Autodesk Fusion 360 part; units mm, degrees
(part 2 of 3)
  spline S265 degree 3 poles (6.2269, 17.0813) (6.3936, 17.4543) (6.4412, 17.5178) (6.6238, 17.8353) knots 0 0 0 0 1 1 1 1
  spline S266 degree 3 poles (6.6238, 17.8353) (6.8064, 18.1528) (7.108, 18.645) (7.3382, 18.9863) knots 0 0 0 0 1 1 1 1
  spline S267 degree 3 poles (7.3382, 18.9863) (7.5684, 19.3276) (7.7985, 19.5975) (8.0129, 19.8594) knots 0 0 0 0 1 1 1 1
  spline S268 degree 3 poles (8.0129, 19.8594) (8.2272, 20.1213) (8.3859, 20.296) (8.6479, 20.5341) knots 0 0 0 0 1 1 1 1
  spline S269 degree 3 poles (8.6479, 20.5341) (8.9098, 20.7722) (9.2273, 21.05) (9.5607, 21.2881) knots 0 0 0 0 1 1 1 1
  spline S270 degree 3 poles (9.5607, 21.2881) (9.894, 21.5263) (10.2354, 21.7485) (10.6322, 21.9628) knots 0 0 0 0 1 1 1 1
  spline S271 degree 3 poles (10.6322, 21.9628) (11.0291, 22.1771) (11.4895, 22.3915) (11.9419, 22.5581) knots 0 0 0 0 1 1 1 1
  spline S272 degree 3 poles (11.9419, 22.5581) (12.3944, 22.7248) (12.9817, 22.8677) (13.331, 22.955) knots 0 0 0 0 1 1 1 1
  spline S273 degree 3 poles (13.331, 22.955) (13.6802, 23.0423) (13.7755, 23.0423) (14.0454, 23.0741) knots 0 0 0 0 1 1 1 1
  spline S274 degree 3 poles (14.0454, 23.0741) (14.3152, 23.1058) (14.5772, 23.1455) (14.9582, 23.1535) knots 0 0 0 0 1 1 1 1
  spline S275 degree 3 poles (14.9582, 23.1535) (15.3392, 23.1614) (16.0059, 23.1376) (16.3472, 23.1138) knots 0 0 0 0 1 1 1 1
  spline S276 degree 3 poles (16.3472, 23.1138) (16.6885, 23.09) (16.6489, 23.1217) (17.0219, 23.0344) knots 0 0 0 0 1 1 1 1
  spline S277 degree 3 poles (17.0219, 23.0344) (17.395, 22.9471) (18.1411, 22.7486) (18.5697, 22.5978) knots 0 0 0 0 1 1 1 1
  spline S278 degree 3 poles (18.5697, 22.5978) (18.9984, 22.447) (19.2524, 22.3121) (19.6016, 22.1216) knots 0 0 0 0 1 1 1 1
  spline S279 degree 3 poles (19.6016, 22.1216) (19.9509, 21.9311) (20.3398, 21.6771) (20.6732, 21.4469) knots 0 0 0 0 1 1 1 1
  spline S280 degree 3 poles (20.6732, 21.4469) (21.0065, 21.2167) (21.3002, 20.9786) (21.586, 20.7325) knots 0 0 0 0 1 1 1 1
  spline S281 degree 3 poles (21.586, 20.7325) (21.8717, 20.4865) (22.1337, 20.2325) (22.3797, 19.9785) knots 0 0 0 0 1 1 1 1
  spline S282 degree 3 poles (22.3797, 19.9785) (22.6258, 19.7245) (22.7925, 19.534) (23.0544, 19.1847) knots 0 0 0 0 1 1 1 1
  spline S283 degree 3 poles (23.0544, 19.1847) (23.3164, 18.8355) (23.6974, 18.3195) (23.9672, 17.875) knots 0 0 0 0 1 1 1 1
  spline S284 degree 3 poles (23.9672, 17.875) (24.2371, 17.4305) (24.4911, 16.9305) (24.6816, 16.5256) knots 0 0 0 0 1 1 1 1
  spline S285 degree 3 poles (24.6816, 16.5256) (24.8721, 16.1208) (24.9912, 15.7875) (25.1182, 15.4541) knots 0 0 0 0 1 1 1 1
  spline S286 degree 3 poles (25.1182, 15.4541) (25.2452, 15.1207) (25.3245, 14.9143) (25.4357, 14.5016) knots 0 0 0 0 1 1 1 1
  spline S287 degree 3 poles (25.4357, 14.5016) (25.5468, 14.0888) (25.6897, 13.4856) (25.7929, 12.9538) knots 0 0 0 0 1 1 1 1
  spline S288 degree 3 poles (25.7929, 12.9538) (25.896, 12.422) (25.9754, 11.7711) (26.031, 11.3266) knots 0 0 0 0 1 1 1 1
  spline S289 degree 3 poles (26.031, 11.3266) (26.0865, 10.8821) (26.0945, 10.7868) (26.1104, 10.2947) knots 0 0 0 0 1 1 1 1
  spline S290 degree 3 poles (26.1104, 10.2947) (26.1262, 9.8026) (26.1659, 9.2231) (26.1104, 8.35) knots 0 0 0 0 1 1 1 1
  spline S291 degree 3 poles (26.1104, 8.35) (26.0548, 7.4769) (25.8564, 5.6433) (25.7929, 5.056) knots 0 0 0 0 1 1 1 1
  spline S292 degree 3 poles (25.7929, 5.056) (25.7294, 4.4686) (25.769, 5.1512) (25.7135, 4.8178) knots 0 0 0 0 1 1 1 1
  spline S293 degree 3 poles (25.7135, 4.8178) (25.6579, 4.4845) (25.5468, 3.5081) (25.4754, 3.0319) knots 0 0 0 0 1 1 1 1
  spline S294 degree 3 poles (25.4754, 3.0319) (25.4039, 2.5556) (25.4357, 2.6668) (25.2769, 1.9603) knots 0 0 0 0 1 1 1 1
  spline S295 degree 3 poles (25.2769, 1.9603) (25.1182, 1.2539) (24.7848, -0.2304) (24.5229, -1.2147) knots 0 0 0 0 1 1 1 1
  spline S296 degree 3 poles (24.5229, -1.2147) (24.2609, -2.1989) (23.9672, -3.1355) (23.6894, -3.9531) knots 0 0 0 0 1 1 1 1
  spline S297 degree 3 poles (23.6894, -3.9531) (23.4116, -4.7707) (23.1179, -5.5247) (22.856, -6.1359) knots 0 0 0 0 1 1 1 1
  spline S298 degree 3 poles (22.856, -6.1359) (22.594, -6.7471) (22.4432, -7.0567) (22.1416, -7.6044) knots 0 0 0 0 1 1 1 1
  spline S299 degree 3 poles (22.1416, -7.6044) (21.84, -8.152) (21.3796, -8.914) (21.0304, -9.43) knots 0 0 0 0 1 1 1 1
  spline S300 degree 3 poles (21.0304, -9.43) (20.6811, -9.9459) (20.3715, -10.3269) (20.0382, -10.7) knots 0 0 0 0 1 1 1 1
  spline S301 degree 3 poles (20.0382, -10.7) (19.7048, -11.073) (19.4667, -11.335) (19.046, -11.6922) knots 0 0 0 0 1 1 1 1
  spline S302 degree 3 poles (19.046, -11.6922) (18.6253, -12.0494) (18.0141, -12.5335) (17.5379, -12.8431) knots 0 0 0 0 1 1 1 1
  spline S303 degree 3 poles (17.5379, -12.8431) (17.0616, -13.1527) (16.6012, -13.3749) (16.1885, -13.5575) knots 0 0 0 0 1 1 1 1
  spline S304 degree 3 poles (16.1885, -13.5575) (15.7757, -13.74) (15.4027, -13.8512) (15.0772, -13.9544) knots 0 0 0 0 1 1 1 1
  spline S305 degree 3 poles (15.0772, -13.9544) (14.7518, -14.0575) (14.5851, -14.1052) (14.2438, -14.1528) knots 0 0 0 0 1 1 1 1
  spline S306 degree 3 poles (14.2438, -14.1528) (13.9025, -14.2004) (13.3786, -14.2401) (13.0135, -14.2322) knots 0 0 0 0 1 1 1 1
  spline S307 degree 3 poles (18.411, -26.0987) (19.2603, -25.678) (20.1175, -25.17) (20.7129, -24.8287) knots 0 0 0 0 1 1 1 1
  spline S308 degree 3 poles (20.7129, -24.8287) (21.3082, -24.4874) (21.3796, -24.4557) (21.9829, -24.035) knots 0 0 0 0 1 1 1 1
  spline S309 degree 3 poles (21.9829, -24.035) (22.5861, -23.6143) (23.5783, -22.9237) (24.3244, -22.3284) knots 0 0 0 0 1 1 1 1
  spline S310 degree 3 poles (24.3244, -22.3284) (25.0705, -21.7331) (25.7452, -21.1457) (26.4675, -20.4631) knots 0 0 0 0 1 1 1 1
  spline S311 degree 3 poles (26.4675, -20.4631) (27.1899, -19.7805) (28.1106, -18.82) (28.6504, -18.2406) knots 0 0 0 0 1 1 1 1
  spline S312 degree 3 poles (28.6504, -18.2406) (29.1901, -17.6612) (29.3806, -17.3992) (29.7219, -16.9706) knots 0 0 0 0 1 1 1 1
  spline S313 degree 3 poles (29.7219, -16.9706) (30.0632, -16.542) (30.2775, -16.288) (30.7141, -15.6609) knots 0 0 0 0 1 1 1 1
  spline S314 degree 3 poles (30.7141, -15.6609) (31.1507, -15.0339) (31.8333, -14.0575) (32.3413, -13.2003) knots 0 0 0 0 1 1 1 1
  spline S315 degree 3 poles (32.3413, -13.2003) (32.8493, -12.343) (33.3335, -11.4699) (33.77, -10.5412) knots 0 0 0 0 1 1 1 1
  spline S316 degree 3 poles (33.77, -10.5412) (34.2066, -9.6125) (34.6035, -8.66) (34.9607, -7.644) knots 0 0 0 0 1 1 1 1
  spline S317 degree 3 poles (34.9607, -7.644) (35.3179, -6.628) (35.6592, -5.4454) (35.9132, -4.4294) knots 0 0 0 0 1 1 1 1
  spline S318 degree 3 poles (35.9132, -4.4294) (36.1672, -3.4134) (36.3497, -2.5482) (36.5085, -1.5322) knots 0 0 0 0 1 1 1 1
  spline S319 degree 3 poles (36.5085, -1.5322) (36.6672, -0.5162) (36.8022, 0.5157) (36.8657, 1.6825) knots 0 0 0 0 1 1 1 1
  spline S320 degree 3 poles (36.8657, 1.6825) (36.9292, 2.8493) (36.953, 4.294) (36.9054, 5.4528) knots 0 0 0 0 1 1 1 1
  spline S321 degree 3 poles (36.9054, 5.4528) (36.8577, 6.6117) (36.691, 7.8261) (36.5879, 8.6278) knots 0 0 0 0 1 1 1 1
  spline S322 degree 3 poles (36.5879, 8.6278) (36.4847, 9.4295) (36.3894, 9.7311) (36.2704, 10.255) knots 0 0 0 0 1 1 1 1
  spline S323 degree 3 poles (36.2704, 10.255) (36.1513, 10.7789) (36.0799, 11.1043) (35.8735, 11.7631) knots 0 0 0 0 1 1 1 1
  spline S324 degree 3 poles (35.8735, 11.7631) (35.6671, 12.422) (35.4052, 13.3348) (35.04, 14.2238) knots 0 0 0 0 1 1 1 1
  spline S325 degree 3 poles (35.04, 14.2238) (34.6749, 15.1128) (34.1431, 16.232) (33.6907, 17.0813) knots 0 0 0 0 1 1 1 1
  spline S326 degree 3 poles (33.6907, 17.0813) (33.2382, 17.9306) (32.8017, 18.645) (32.3413, 19.3435) knots 0 0 0 0 1 1 1 1
  spline S327 degree 3 poles (32.3413, 19.3435) (31.8809, 20.042) (31.3888, 20.7087) (30.9522, 21.2881) knots 0 0 0 0 1 1 1 1
  spline S328 degree 3 poles (30.9522, 21.2881) (30.5157, 21.8676) (30.341, 22.1375) (29.7219, 22.7963) knots 0 0 0 0 1 1 1 1
  spline S329 degree 3 poles (29.7219, 22.7963) (29.1028, 23.4551) (27.9519, 24.6378) (27.2613, 25.2569) knots 0 0 0 0 1 1 1 1
  spline S330 degree 3 poles (27.2613, 25.2569) (26.5707, 25.876) (26.1818, 26.13) (25.5944, 26.5269) knots 0 0 0 0 1 1 1 1
  spline S331 degree 3 poles (25.5944, 26.5269) (25.007, 26.9238) (24.3085, 27.3365) (23.7291, 27.6381) knots 0 0 0 0 1 1 1 1
  spline S332 degree 3 poles (23.7291, 27.6381) (23.1497, 27.9398) (22.8322, 28.0906) (22.1416, 28.3525) knots 0 0 0 0 1 1 1 1
  spline S333 degree 3 poles (22.1416, 28.3525) (21.451, 28.6145) (20.062, 29.0431) (19.6016, 29.2256) knots 0 0 0 0 1 1 1 1
  spline S334 degree 3 poles (19.6016, 29.2256) (19.1412, 29.4082) (19.419, 29.3447) (19.3635, 29.4241) knots 0 0 0 0 1 1 1 1
  spline S335 degree 3 poles (19.3635, 29.4241) (19.3079, 29.5035) (19.2603, 28.416) (19.2444, 29.7019) knots 0 0 0 0 1 1 1 1
  spline S336 degree 3 poles (19.2444, 29.7019) (19.2285, 30.9878) (19.2285, 35.1232) (19.2444, 37.1235) knots 0 0 0 0 1 1 1 1
  spline S337 degree 3 poles (19.2444, 37.1235) (19.2603, 39.1237) (19.3317, 40.8223) (19.3238, 41.6875) knots 0 0 0 0 1 1 1 1
  spline S338 degree 3 poles (19.3238, 41.6875) (19.3159, 42.5527) (19.2762, 42.1161) (19.2047, 42.3225) knots 0 0 0 0 1 1 1 1
  spline S339 degree 3 poles (19.2047, 42.3225) (19.1333, 42.5289) (19.0142, 42.7511) (18.8872, 42.9178) knots 0 0 0 0 1 1 1 1
  spline S340 degree 3 poles (18.8872, 42.9178) (18.7602, 43.0845) (18.6015, 43.2195) (18.4507, 43.3147) knots 0 0 0 0 1 1 1 1
  spline S341 degree 3 poles (18.4507, 43.3147) (18.2999, 43.41) (18.1173, 43.4655) (17.9744, 43.5131) knots 0 0 0 0 1 1 1 1
  spline S342 degree 3 poles (17.9744, 43.5131) (17.8315, 43.5608) (18.3951, 43.5767) (17.5775, 43.5925) knots 0 0 0 0 1 1 1 1
  spline S343 degree 3 poles (17.5775, 43.5925) (16.76, 43.6084) (13.8787, 43.6163) (13.0532, 43.5925) knots 0 0 0 0 1 1 1 1
  spline S344 degree 3 poles (13.0532, 43.5925) (12.2277, 43.5687) (12.7515, 43.537) (12.6166, 43.4338) knots 0 0 0 0 1 1 1 1
  spline S345 degree 3 poles (12.6166, 43.4338) (12.4817, 43.3306) (12.3229, 43.156) (12.2197, 42.9575) knots 0 0 0 0 1 1 1 1
  spline S346 degree 3 poles (12.2197, 42.9575) (12.1165, 42.7591) (12.0927, 43.1242) (12.0213, 42.2431) knots 0 0 0 0 1 1 1 1
  spline S347 degree 3 poles (12.0213, 42.2431) (11.9499, 41.3621) (11.8467, 38.4808) (11.7832, 37.6791) knots 0 0 0 0 1 1 1 1
  spline S348 degree 3 poles (11.7832, 37.6791) (11.7197, 36.8774) (11.7435, 37.5203) (11.6641, 37.441) knots 0 0 0 0 1 1 1 1
  spline S349 degree 3 poles (11.6641, 37.441) (11.5847, 37.3616) (11.4022, 37.2425) (11.3069, 37.2028) knots 0 0 0 0 1 1 1 1
  spline S350 degree 3 poles (11.3069, 37.2028) (11.2117, 37.1631) (11.1402, 37.187) (11.0688, 37.2028) knots 0 0 0 0 1 1 1 1
  spline S351 degree 3 poles (11.0688, 37.2028) (10.9974, 37.2187) (10.9339, 37.2346) (10.8704, 37.2822) knots 0 0 0 0 1 1 1 1
  spline S352 degree 3 poles (10.8704, 37.2822) (10.8069, 37.3298) (10.7275, 37.4013) (10.6719, 37.4806) knots 0 0 0 0 1 1 1 1
  spline S353 degree 3 poles (10.6719, 37.4806) (10.6164, 37.56) (10.6164, 36.9965) (10.5529, 37.7585) knots 0 0 0 0 1 1 1 1
  spline S354 degree 3 poles (10.5529, 37.7585) (10.4894, 38.5205) (10.3385, 41.2113) (10.275, 42.0447) knots 0 0 0 0 1 1 1 1
  spline S355 degree 3 poles (10.275, 42.0447) (10.2115, 42.8781) (10.2036, 42.5845) (10.156, 42.7591) knots 0 0 0 0 1 1 1 1
  spline S356 degree 3 poles (10.156, 42.7591) (10.1084, 42.9337) (10.0687, 42.9813) (9.9972, 43.0766) knots 0 0 0 0 1 1 1 1
  spline S357 degree 3 poles (9.9972, 43.0766) (9.9258, 43.1718) (9.8623, 43.2671) (9.7194, 43.3544) knots 0 0 0 0 1 1 1 1
  spline S358 degree 3 poles (9.7194, 43.3544) (9.5765, 43.4417) (10.4259, 43.5528) (9.1638, 43.5925) knots 0 0 0 0 1 1 1 1
  spline S359 degree 3 poles (9.1638, 43.5925) (7.9017, 43.6322) (3.3853, 43.6163) (2.1391, 43.5925) knots 0 0 0 0 1 1 1 1
  spline S360 degree 3 poles (2.1391, 43.5925) (0.8929, 43.5687) (1.7819, 43.4893) (1.6629, 43.4338) knots 0 0 0 0 1 1 1 1
  spline S361 degree 3 poles (1.6629, 43.4338) (1.5438, 43.3782) (1.4882, 43.3068) (1.4247, 43.2353) knots 0 0 0 0 1 1 1 1
  spline S362 degree 3 poles (1.4247, 43.2353) (1.3612, 43.1639) (1.3215, 43.148) (1.266, 42.9972) knots 0 0 0 0 1 1 1 1
  spline S363 degree 3 poles (1.266, 42.9972) (1.2104, 42.8464) (1.131, 42.8543) (1.0675, 42.3225) knots 0 0 0 0 1 1 1 1
  spline S364 degree 3 poles (1.0675, 42.3225) (1.004, 41.7907) (0.9167, 40.5286) (0.8691, 39.7825) knots 0 0 0 0 1 1 1 1
  spline S365 degree 3 poles (0.8691, 39.7825) (0.8215, 39.0364) (0.8215, 38.2188) (0.7897, 37.8378) knots 0 0 0 0 1 1 1 1
  spline S366 degree 3 poles (0.7897, 37.8378) (0.758, 37.4568) (0.7342, 37.6156) (0.6707, 37.5203) knots 0 0 0 0 1 1 1 1
  spline S367 degree 3 poles (0.6707, 37.5203) (0.6072, 37.4251) (0.504, 37.3378) (0.4325, 37.2822) knots 0 0 0 0 1 1 1 1
  spline S368 degree 3 poles (0.4325, 37.2822) (0.3611, 37.2267) (0.3214, 37.2187) (0.2341, 37.2028) knots 0 0 0 0 1 1 1 1
  spline S369 degree 3 poles (0.2341, 37.2028) (0.1468, 37.187) (0.0039, 37.187) (-0.0834, 37.2028) knots 0 0 0 0 1 1 1 1
  spline S370 degree 3 poles (-0.0834, 37.2028) (-0.1707, 37.2187) (-0.2025, 37.2187) (-0.2818, 37.2822) knots 0 0 0 0 1 1 1 1
  spline S371 degree 3 poles (-0.2818, 37.2822) (-0.3612, 37.3457) (-0.5041, 37.4727) (-0.5596, 37.56) knots 0 0 0 0 1 1 1 1
  spline S372 degree 3 poles (-0.5596, 37.56) (-0.6152, 37.6473) (-0.5835, 37.0282) (-0.639, 37.7981) knots 0 0 0 0 1 1 1 1
  spline S373 degree 3 poles (-0.639, 37.7981) (-0.6946, 38.5681) (-0.8533, 41.3303) (-0.9168, 42.1638) knots 0 0 0 0 1 1 1 1
  spline S374 degree 3 poles (-0.9168, 42.1638) (-0.9803, 42.9972) (-0.9803, 42.6321) (-1.0359, 42.7988) knots 0 0 0 0 1 1 1 1
  spline S375 degree 3 poles (-1.0359, 42.7988) (-1.0915, 42.9655) (-1.1708, 43.0686) (-1.2343, 43.156) knots 0 0 0 0 1 1 1 1
  spline S376 degree 3 poles (-1.2343, 43.156) (-1.2978, 43.2433) (-1.2661, 43.2433) (-1.3931, 43.3147) knots 0 0 0 0 1 1 1 1
  spline S377 degree 3 poles (-1.3931, 43.3147) (-1.5201, 43.3861) (-0.6946, 43.5449) (-1.9884, 43.5925) knots 0 0 0 0 1 1 1 1
  spline S378 degree 3 poles (-1.9884, 43.5925) (-3.2822, 43.6401) (-7.8463, 43.6322) (-9.1321, 43.5925) knots 0 0 0 0 1 1 1 1
  spline S379 degree 3 poles (-9.1321, 43.5925) (-10.418, 43.5528) (-9.5528, 43.4496) (-9.6878, 43.3544) knots 0 0 0 0 1 1 1 1
  spline S380 degree 3 poles (-9.6878, 43.3544) (-9.8227, 43.2592) (-9.8783, 43.2115) (-9.9656, 43.0369) knots 0 0 0 0 1 1 1 1
  spline S381 degree 3 poles (-9.9656, 43.0369) (-10.0529, 42.8623) (-10.1085, 43.2036) (-10.2037, 42.3225) knots 0 0 0 0 1 1 1 1
  spline S382 degree 3 poles (-10.2037, 42.3225) (-10.299, 41.4415) (-10.4815, 38.5681) (-10.5609, 37.7585) knots 0 0 0 0 1 1 1 1
  spline S383 degree 3 poles (-10.5609, 37.7585) (-10.6403, 36.9488) (-10.6323, 37.5521) (-10.68, 37.4806) knots 0 0 0 0 1 1 1 1
  spline S384 degree 3 poles (-10.68, 37.4806) (-10.7276, 37.4092) (-10.7673, 37.3695) (-10.8387, 37.3219) knots 0 0 0 0 1 1 1 1
  spline S385 degree 3 poles (-10.8387, 37.3219) (-10.9101, 37.2743) (-11.0133, 37.2187) (-11.1165, 37.2028) knots 0 0 0 0 1 1 1 1
  spline S386 degree 3 poles (-11.1165, 37.2028) (-11.2197, 37.187) (-11.3308, 37.187) (-11.434, 37.2425) knots 0 0 0 0 1 1 1 1
  spline S387 degree 3 poles (-11.434, 37.2425) (-11.5372, 37.2981) (-11.688, 37.441) (-11.7515, 37.5203) knots 0 0 0 0 1 1 1 1
  spline S388 degree 3 poles (-11.7515, 37.5203) (-11.815, 37.5997) (-11.7753, 36.9012) (-11.8309, 37.7188) knots 0 0 0 0 1 1 1 1
  spline S389 degree 3 poles (-11.8309, 37.7188) (-11.8865, 38.5363) (-12.0214, 41.5526) (-12.1087, 42.4416) knots 0 0 0 0 1 1 1 1
  spline S390 degree 3 poles (-12.1087, 42.4416) (-12.196, 43.3306) (-12.2516, 42.8861) (-12.3468, 43.0369) knots 0 0 0 0 1 1 1 1
  spline S391 degree 3 poles (-12.3468, 43.0369) (-12.4421, 43.1877) (-12.5135, 43.2592) (-12.6643, 43.3544) knots 0 0 0 0 1 1 1 1
  spline S392 degree 3 poles (-12.6643, 43.3544) (-12.8151, 43.4496) (-12.4421, 43.5528) (-13.2596, 43.5925) knots 0 0 0 0 1 1 1 1
  spline S393 degree 3 poles (-13.2596, 43.5925) (-14.0772, 43.6322) (-16.7918, 43.6084) (-17.5856, 43.5925) knots 0 0 0 0 1 1 1 1
  spline S394 degree 3 poles (-17.5856, 43.5925) (-18.3793, 43.5767) (-17.8555, 43.5687) (-18.0221, 43.5131) knots 0 0 0 0 1 1 1 1
  spline S395 degree 3 poles (-18.0221, 43.5131) (-18.1888, 43.4576) (-18.419, 43.3782) (-18.5778, 43.275) knots 0 0 0 0 1 1 1 1
  spline S396 degree 3 poles (-18.5778, 43.275) (-18.7365, 43.1718) (-18.8556, 43.0686) (-18.9746, 42.9178) knots 0 0 0 0 1 1 1 1
  spline S397 degree 3 poles (-18.9746, 42.9178) (-19.0937, 42.767) (-19.2207, 42.5368) (-19.2921, 42.3622) knots 0 0 0 0 1 1 1 1
  spline S398 degree 3 poles (-19.2921, 42.3622) (-19.3636, 42.1876) (-19.3953, 42.8067) (-19.4112, 41.8463) knots 0 0 0 0 1 1 1 1
  spline S399 degree 3 poles (-19.4112, 41.8463) (-19.4271, 40.8858) (-19.3953, 37.9013) (-19.3715, 36.6075) knots 0 0 0 0 1 1 1 1
  spline S400 degree 3 poles (-19.3715, 36.6075) (-19.3477, 35.3137) (-19.308, 35.1946) (-19.2921, 34.0675) knots 0 0 0 0 1 1 1 1
  spline S401 degree 3 poles (-19.2921, 34.0675) (-19.2763, 32.9404) (-19.2683, 30.6147) (-19.2921, 29.8606) knots 0 0 0 0 1 1 1 1
  spline S402 degree 3 poles (-19.2921, 29.8606) (-19.316, 29.1066) (-19.3398, 29.6463) (-19.4112, 29.5431) knots 0 0 0 0 1 1 1 1
  spline S403 degree 3 poles (-19.4112, 29.5431) (-19.4826, 29.44) (-19.3001, 29.44) (-19.7287, 29.2653) knots 0 0 0 0 1 1 1 1
  spline S404 degree 3 poles (-19.7287, 29.2653) (-20.1573, 29.0907) (-21.4194, 28.7176) (-21.9909, 28.5113) knots 0 0 0 0 1 1 1 1
  spline S405 degree 3 poles (-21.9909, 28.5113) (-22.5624, 28.3049) (-22.6021, 28.297) (-23.1418, 28.035) knots 0 0 0 0 1 1 1 1
  spline S406 degree 3 poles (-23.1418, 28.035) (-23.6816, 27.7731) (-24.769, 27.1698) (-25.2056, 26.9238) knots 0 0 0 0 1 1 1 1
  spline S407 degree 3 poles (-25.2056, 26.9238) (-25.6421, 26.6777) (-25.412, 26.8206) (-25.7612, 26.5666) knots 0 0 0 0 1 1 1 1
  spline S408 degree 3 poles (-25.7612, 26.5666) (-26.1105, 26.3126) (-26.9121, 25.7014) (-27.309, 25.376) knots 0 0 0 0 1 1 1 1
  spline S409 degree 3 poles (-27.309, 25.376) (-27.7059, 25.0505) (-27.7853, 24.9711) (-28.1425, 24.6219) knots 0 0 0 0 1 1 1 1
  spline S410 degree 3 poles (-28.1425, 24.6219) (-28.4996, 24.2726) (-29.0394, 23.725) (-29.4521, 23.2725) knots 0 0 0 0 1 1 1 1
  spline S411 degree 3 poles (-29.4521, 23.2725) (-29.8649, 22.8201) (-30.2618, 22.328) (-30.6031, 21.8835) knots 0 0 0 0 1 1 1 1
  spline S412 degree 3 poles (-30.6031, 21.8835) (-30.9444, 21.439) (-31.1746, 21.1215) (-31.5159, 20.6135) knots 0 0 0 0 1 1 1 1
  spline S413 degree 3 poles (-31.5159, 20.6135) (-31.8572, 20.1055) (-32.3811, 19.2879) (-32.6668, 18.8275) knots 0 0 0 0 1 1 1 1
  spline S414 degree 3 poles (-32.6668, 18.8275) (-32.9526, 18.3671) (-32.9288, 18.4227) (-33.2225, 17.8353) knots 0 0 0 0 1 1 1 1
  spline S415 degree 3 poles (-33.2225, 17.8353) (-33.5161, 17.248) (-34.1432, 15.9145) (-34.4131, 15.2953) knots 0 0 0 0 1 1 1 1
  spline S416 degree 3 poles (-34.4131, 15.2953) (-34.683, 14.6762) (-34.6671, 14.6921) (-34.8496, 14.1444) knots 0 0 0 0 1 1 1 1
  spline S417 degree 3 poles (-34.8496, 14.1444) (-35.0322, 13.5967) (-35.2941, 12.7791) (-35.4846, 12.0013) knots 0 0 0 0 1 1 1 1
  spline S418 degree 3 poles (-35.4846, 12.0013) (-35.6751, 11.2234) (-35.8577, 10.4376) (-36.0006, 9.4613) knots 0 0 0 0 1 1 1 1
  spline S419 degree 3 poles (-36.0006, 9.4613) (-36.1435, 8.485) (-36.2625, 7.2467) (-36.3181, 6.1672) knots 0 0 0 0 1 1 1 1
  spline S420 degree 3 poles (-36.3181, 6.1672) (-36.3736, 5.0877) (-36.3736, 4.1193) (-36.3181, 2.9922) knots 0 0 0 0 1 1 1 1
  spline S421 degree 3 poles (-36.3181, 2.9922) (-36.2625, 1.8651) (-36.0958, 0.23) (-36.0006, -0.6194) knots 0 0 0 0 1 1 1 1
  spline S422 degree 3 poles (-36.0006, -0.6194) (-35.9053, -1.4687) (-35.8736, -1.5322) (-35.7625, -2.1275) knots 0 0 0 0 1 1 1 1
  spline S423 degree 3 poles (-35.7625, -2.1275) (-35.6513, -2.7228) (-35.5164, -3.4054) (-35.3259, -4.1912) knots 0 0 0 0 1 1 1 1
  spline S424 degree 3 poles (-35.3259, -4.1912) (-35.1354, -4.977) (-34.9211, -5.8819) (-34.6115, -6.8503) knots 0 0 0 0 1 1 1 1
  spline S425 degree 3 poles (-34.6115, -6.8503) (-34.302, -7.8187) (-33.8733, -8.9855) (-33.4606, -9.9856) knots 0 0 0 0 1 1 1 1
  spline S426 degree 3 poles (-33.4606, -9.9856) (-33.0478, -10.9857) (-32.4922, -12.097) (-32.1112, -12.8431) knots 0 0 0 0 1 1 1 1
  spline S427 degree 3 poles (-32.1112, -12.8431) (-31.7302, -13.5892) (-31.508, -13.9464) (-31.1984, -14.4703) knots 0 0 0 0 1 1 1 1
  spline S428 degree 3 poles (-31.1984, -14.4703) (-30.8888, -14.9942) (-30.4602, -15.6609) (-30.2459, -15.9784) knots 0 0 0 0 1 1 1 1
  spline S429 degree 3 poles (-30.2459, -15.9784) (-30.0316, -16.2959) (-30.0554, -16.1927) (-29.9284, -16.3753) knots 0 0 0 0 1 1 1 1
  spline S430 degree 3 poles (-29.9284, -16.3753) (-29.8014, -16.5579) (-29.7458, -16.7245) (-29.4918, -17.0897) knots 0 0 0 0 1 1 1 1
  spline S431 degree 3 poles (-29.4918, -17.0897) (-29.2378, -17.4548) (-28.841, -17.9945) (-28.3806, -18.5581) knots 0 0 0 0 1 1 1 1
  spline S432 degree 3 poles (-28.3806, -18.5581) (-27.9202, -19.1217) (-27.2058, -19.9313) (-26.7137, -20.4631) knots 0 0 0 0 1 1 1 1
  spline S433 degree 3 poles (-26.7137, -20.4631) (-26.2216, -20.9949) (-25.8406, -21.36) (-25.4437, -21.7331) knots 0 0 0 0 1 1 1 1
  spline S434 degree 3 poles (-25.4437, -21.7331) (-25.0468, -22.1062) (-24.7135, -22.4078) (-24.3325, -22.7253) knots 0 0 0 0 1 1 1 1
  spline S435 degree 3 poles (-24.3325, -22.7253) (-23.9515, -23.0428) (-23.7133, -23.2571) (-23.1815, -23.6381) knots 0 0 0 0 1 1 1 1
  spline S436 degree 3 poles (-23.1815, -23.6381) (-22.6497, -24.0191) (-21.8004, -24.6224) (-21.1575, -25.0272) knots 0 0 0 0 1 1 1 1
  spline S437 degree 3 poles (-21.1575, -25.0272) (-20.5145, -25.432) (-19.8636, -25.7733) (-19.3318, -26.059) knots 0 0 0 0 1 1 1 1
  spline S438 degree 3 poles (-19.3318, -26.059) (-18.8, -26.3448) (-18.5619, -26.4718) (-17.9825, -26.7337) knots 0 0 0 0 1 1 1 1
  spline S439 degree 3 poles (-17.9825, -26.7337) (-17.403, -26.9957) (-16.5378, -27.3767) (-15.8393, -27.6465) knots 0 0 0 0 1 1 1 1
  spline S440 degree 3 poles (-15.8393, -27.6465) (-15.1408, -27.9164) (-14.482, -28.1387) (-13.8153, -28.3609) knots 0 0 0 0 1 1 1 1
  spline S441 degree 3 poles (-13.8153, -28.3609) (-13.1485, -28.5832) (-12.458, -28.7816) (-11.8309, -28.9562) knots 0 0 0 0 1 1 1 1
  spline S442 degree 3 poles (-11.8309, -28.9562) (-11.2038, -29.1309) (-10.6958, -29.2499) (-10.045, -29.3928) knots 0 0 0 0 1 1 1 1
  spline S443 degree 3 poles (-10.045, -29.3928) (-9.3941, -29.5357) (-8.5606, -29.6865) (-7.9415, -29.7897) knots 0 0 0 0 1 1 1 1
  spline S444 degree 3 poles (-7.9415, -29.7897) (-7.3224, -29.8929) (-6.9176, -29.9564) (-6.3143, -30.0278) knots 0 0 0 0 1 1 1 1
  spline S445 degree 3 poles (-6.3143, -30.0278) (-5.7111, -30.0992) (-5.0761, -30.1707) (-4.33, -30.2262) knots 0 0 0 0 1 1 1 1
  spline S446 degree 3 poles (-4.33, -30.2262) (-3.5838, -30.2818) (-2.5758, -30.3294) (-1.8296, -30.3453) knots 0 0 0 0 1 1 1 1
  spline S447 degree 3 poles (-1.8296, -30.3453) (-1.0835, -30.3612) (-0.6152, -30.3612) (0.1547, -30.3453) knots 0 0 0 0 1 1 1 1
  spline S448 degree 3 poles (0.1547, -30.3453) (0.9247, -30.3294) (1.8613, -30.2897) (2.7741, -30.2262) knots 0 0 0 0 1 1 1 1
  spline S449 degree 3 poles (2.7741, -30.2262) (3.6869, -30.1627) (4.7585, -30.0595) (5.6316, -29.9484) knots 0 0 0 0 1 1 1 1
  spline S450 degree 3 poles (5.6316, -29.9484) (6.5047, -29.8373) (7.3858, -29.6627) (8.0129, -29.5515) knots 0 0 0 0 1 1 1 1
  spline S451 degree 3 poles (8.0129, -29.5515) (8.6399, -29.4404) (8.7114, -29.4404) (9.4019, -29.2737) knots 0 0 0 0 1 1 1 1
  spline S452 degree 3 poles (9.4019, -29.2737) (10.0925, -29.107) (11.1085, -28.8769) (12.1404, -28.5594) knots 0 0 0 0 1 1 1 1
  spline S453 degree 3 poles (12.1404, -28.5594) (13.1722, -28.2419) (14.5454, -27.7815) (15.5932, -27.3687) knots 0 0 0 0 1 1 1 1
  spline S454 degree 3 poles (15.5932, -27.3687) (16.6409, -26.956) (17.5617, -26.5194) (18.411, -26.0987) knots 0 0 0 0 1 1 1 1
  spline S455 degree 3 poles (19.2841, -24.8684) (18.657, -25.2335) (18.4665, -25.3288) (17.9347, -25.5828) knots 0 0 0 0 1 1 1 1
  spline S456 degree 3 poles (17.9347, -25.5828) (17.4029, -25.8368) (16.7917, -26.1305) (16.1091, -26.4162) knots 0 0 0 0 1 1 1 1
  spline S457 degree 3 poles (16.1091, -26.4162) (15.4265, -26.702) (14.5454, -27.0354) (13.8469, -27.2894) knots 0 0 0 0 1 1 1 1
  spline S458 degree 3 poles (13.8469, -27.2894) (13.1484, -27.5434) (12.7515, -27.6862) (11.9022, -27.9244) knots 0 0 0 0 1 1 1 1
  spline S459 degree 3 poles (11.9022, -27.9244) (11.0529, -28.1625) (9.894, -28.48) (8.7272, -28.7181) knots 0 0 0 0 1 1 1 1
  spline S460 degree 3 poles (8.7272, -28.7181) (7.5604, -28.9562) (6.0523, -29.2023) (4.8775, -29.3531) knots 0 0 0 0 1 1 1 1
  spline S461 degree 3 poles (4.8775, -29.3531) (3.7028, -29.5039) (2.8297, -29.5754) (1.6629, -29.6309) knots 0 0 0 0 1 1 1 1
  spline S462 degree 3 poles (1.6629, -29.6309) (0.496, -29.6865) (-1.1311, -29.6865) (-2.1075, -29.6706) knots 0 0 0 0 1 1 1 1
  spline S463 degree 3 poles (-2.1075, -29.6706) (-3.0838, -29.6547) (-3.5203, -29.6071) (-4.2109, -29.5515) knots 0 0 0 0 1 1 1 1
  spline S464 degree 3 poles (-4.2109, -29.5515) (-4.9015, -29.496) (-5.6158, -29.4245) (-6.235, -29.3531) knots 0 0 0 0 1 1 1 1
  spline S465 degree 3 poles (-6.235, -29.3531) (-6.8541, -29.2817) (-7.2827, -29.2182) (-7.9018, -29.115) knots 0 0 0 0 1 1 1 1
  spline S466 degree 3 poles (-7.9018, -29.115) (-8.521, -29.0118) (-9.0607, -28.9324) (-9.9656, -28.7181) knots 0 0 0 0 1 1 1 1
  spline S467 degree 3 poles (-9.9656, -28.7181) (-10.8705, -28.5038) (-12.45, -28.0672) (-13.339, -27.8053) knots 0 0 0 0 1 1 1 1
  spline S468 degree 3 poles (-13.339, -27.8053) (-14.228, -27.5434) (-14.7043, -27.3449) (-15.2837, -27.1306) knots 0 0 0 0 1 1 1 1
  spline S469 degree 3 poles (-15.2837, -27.1306) (-15.8631, -26.9163) (-16.3553, -26.702) (-16.8315, -26.4956) knots 0 0 0 0 1 1 1 1
  spline S470 degree 3 poles (-16.8315, -26.4956) (-17.3078, -26.2892) (-17.6332, -26.1543) (-18.1412, -25.9003) knots 0 0 0 0 1 1 1 1
  spline S471 degree 3 poles (-18.1412, -25.9003) (-18.6492, -25.6463) (-19.4112, -25.2494) (-19.8875, -24.9875) knots 0 0 0 0 1 1 1 1
  spline S472 degree 3 poles (-19.8875, -24.9875) (-20.3637, -24.7255) (-20.5383, -24.6144) (-20.9987, -24.3128) knots 0 0 0 0 1 1 1 1
  spline S473 degree 3 poles (-20.9987, -24.3128) (-21.4591, -24.0112) (-22.1258, -23.5667) (-22.6259, -23.2015) knots 0 0 0 0 1 1 1 1
  spline S474 degree 3 poles (-22.6259, -23.2015) (-23.126, -22.8364) (-23.4752, -22.5665) (-23.9753, -22.13) knots 0 0 0 0 1 1 1 1
  spline S475 degree 3 poles (-23.9753, -22.13) (-24.4753, -21.6934) (-25.0548, -21.1854) (-25.6421, -20.5822) knots 0 0 0 0 1 1 1 1
  spline S476 degree 3 poles (-25.6421, -20.5822) (-26.2295, -19.9789) (-26.9121, -19.2407) (-27.5075, -18.5184) knots 0 0 0 0 1 1 1 1
  spline S477 degree 3 poles (-27.5075, -18.5184) (-28.1028, -17.7961) (-28.7933, -16.8357) (-29.214, -16.2562) knots 0 0 0 0 1 1 1 1
  spline S478 degree 3 poles (-29.214, -16.2562) (-29.6347, -15.6768) (-29.6506, -15.645) (-30.0078, -15.0656) knots 0 0 0 0 1 1 1 1
  spline S479 degree 3 poles (-30.0078, -15.0656) (-30.365, -14.4862) (-30.9285, -13.5734) (-31.3571, -12.7637) knots 0 0 0 0 1 1 1 1
  spline S480 degree 3 poles (-31.3571, -12.7637) (-31.7858, -11.9541) (-32.2223, -11.0492) (-32.5875, -10.2237) knots 0 0 0 0 1 1 1 1
  spline S481 degree 3 poles (-32.5875, -10.2237) (-32.9526, -9.3982) (-33.2145, -8.7553) (-33.54, -7.8028) knots 0 0 0 0 1 1 1 1
  spline S482 degree 3 poles (-33.54, -7.8028) (-33.8654, -6.8503) (-34.2623, -5.5882) (-34.5321, -4.5087) knots 0 0 0 0 1 1 1 1
  spline S483 degree 3 poles (-34.5321, -4.5087) (-34.802, -3.4292) (-34.9925, -2.4212) (-35.1671, -1.3337) knots 0 0 0 0 1 1 1 1
  spline S484 degree 3 poles (-35.1671, -1.3337) (-35.3418, -0.2463) (-35.4846, 1.2221) (-35.564, 2.0397) knots 0 0 0 0 1 1 1 1
  spline S485 degree 3 poles (-35.564, 2.0397) (-35.6434, 2.8573) (-35.6275, 3.0081) (-35.6434, 3.5875) knots 0 0 0 0 1 1 1 1
  spline S486 degree 3 poles (-35.6434, 3.5875) (-35.6593, 4.167) (-35.6672, 4.8099) (-35.6434, 5.5322) knots 0 0 0 0 1 1 1 1
  spline S487 degree 3 poles (-35.6434, 5.5322) (-35.6196, 6.2545) (-35.5402, 7.2626) (-35.4846, 7.9135) knots 0 0 0 0 1 1 1 1
  spline S488 degree 3 poles (-35.4846, 7.9135) (-35.4291, 8.5643) (-35.3814, 8.8263) (-35.2862, 9.4216) knots 0 0 0 0 1 1 1 1
  spline S489 degree 3 poles (-35.2862, 9.4216) (-35.191, 10.0169) (-35.0163, 10.9138) (-34.8893, 11.4853) knots 0 0 0 0 1 1 1 1
  spline S490 degree 3 poles (-34.8893, 11.4853) (-34.7623, 12.0568) (-34.675, 12.3505) (-34.5321, 12.8347) knots 0 0 0 0 1 1 1 1
  spline S491 degree 3 poles (-34.5321, 12.8347) (-34.3893, 13.3189) (-34.2385, 13.7951) (-34.0162, 14.3825) knots 0 0 0 0 1 1 1 1
  spline S492 degree 3 poles (-34.0162, 14.3825) (-33.7939, 14.9699) (-33.405, 15.8668) (-33.1828, 16.3669) knots 0 0 0 0 1 1 1 1
  spline S493 degree 3 poles (-33.1828, 16.3669) (-32.9605, 16.867) (-32.8891, 16.9781) (-32.6668, 17.3988) knots 0 0 0 0 1 1 1 1
  spline S494 degree 3 poles (-32.6668, 17.3988) (-32.4446, 17.8195) (-32.1191, 18.3989) (-31.8334, 18.8672) knots 0 0 0 0 1 1 1 1
  spline S495 degree 3 poles (-31.8334, 18.8672) (-31.5476, 19.3355) (-31.3016, 19.7324) (-30.9603, 20.2166) knots 0 0 0 0 1 1 1 1
  spline S496 degree 3 poles (-30.9603, 20.2166) (-30.619, 20.7008) (-30.1586, 21.3199) (-29.8093, 21.7644) knots 0 0 0 0 1 1 1 1
  spline S497 degree 3 poles (-29.8093, 21.7644) (-29.4601, 22.2089) (-29.2061, 22.4946) (-28.8568, 22.8756) knots 0 0 0 0 1 1 1 1
  spline S498 degree 3 poles (-28.8568, 22.8756) (-28.5076, 23.2566) (-28.079, 23.7011) (-27.7059, 24.0663) knots 0 0 0 0 1 1 1 1
  spline S499 degree 3 poles (-27.7059, 24.0663) (-27.3328, 24.4314) (-26.9042, 24.7965) (-26.5946, 25.0585) knots 0 0 0 0 1 1 1 1
  spline S500 degree 3 poles (-26.5946, 25.0585) (-26.2851, 25.3204) (-26.1501, 25.4315) (-25.8406, 25.6538) knots 0 0 0 0 1 1 1 1
  spline S501 degree 3 poles (-25.8406, 25.6538) (-25.531, 25.876) (-25.031, 26.2173) (-24.7293, 26.4078) knots 0 0 0 0 1 1 1 1
  spline S502 degree 3 poles (-24.7293, 26.4078) (-24.4277, 26.5983) (-24.4833, 26.5825) (-24.0546, 26.8047) knots 0 0 0 0 1 1 1 1
  spline S503 degree 3 poles (-24.0546, 26.8047) (-23.626, 27.027) (-22.9275, 27.408) (-22.1496, 27.7175) knots 0 0 0 0 1 1 1 1
  spline S504 degree 3 poles (-22.1496, 27.7175) (-21.3718, 28.0271) (-19.8954, 28.4795) (-19.3715, 28.67) knots 0 0 0 0 1 1 1 1
  spline S505 degree 3 poles (-19.3715, 28.67) (-18.8476, 28.8605) (-19.1175, 28.7732) (-19.0143, 28.8685) knots 0 0 0 0 1 1 1 1
  spline S506 degree 3 poles (-19.0143, 28.8685) (-18.9111, 28.9637) (-18.8, 29.0907) (-18.7365, 29.2256) knots 0 0 0 0 1 1 1 1
  spline S507 degree 3 poles (-18.7365, 29.2256) (-18.673, 29.3606) (-18.6413, 29.4876) (-18.6175, 29.6622) knots 0 0 0 0 1 1 1 1
  spline S508 degree 3 poles (-18.6175, 29.6622) (-18.5936, 29.8368) (-18.5619, 28.2255) (-18.5778, 30.2575) knots 0 0 0 0 1 1 1 1
  spline S509 degree 3 poles (-18.5778, 30.2575) (-18.5936, 32.2895) (-18.7127, 39.8301) (-18.6968, 41.8463) knots 0 0 0 0 1 1 1 1
  spline S510 degree 3 poles (-18.6968, 41.8463) (-18.681, 43.8624) (-18.6016, 42.2114) (-18.4984, 42.3622) knots 0 0 0 0 1 1 1 1
  spline S511 degree 3 poles (-18.4984, 42.3622) (-18.3952, 42.513) (-18.2047, 42.6718) (-18.0618, 42.7591) knots 0 0 0 0 1 1 1 1
  spline S512 degree 3 poles (-18.0618, 42.7591) (-17.919, 42.8464) (-18.4428, 42.8623) (-17.6253, 42.8781) knots 0 0 0 0 1 1 1 1
  spline S513 degree 3 poles (-17.6253, 42.8781) (-16.8077, 42.894) (-13.9185, 42.8781) (-13.1406, 42.8385) knots 0 0 0 0 1 1 1 1
  spline S514 degree 3 poles (-13.1406, 42.8385) (-12.3627, 42.7988) (-12.9977, 42.7273) (-12.9421, 42.64) knots 0 0 0 0 1 1 1 1
  spline S515 degree 3 poles (-12.9421, 42.64) (-12.8866, 42.5527) (-12.8866, 42.9575) (-12.8231, 42.3225) knots 0 0 0 0 1 1 1 1
  spline S516 degree 3 poles (-12.8231, 42.3225) (-12.7596, 41.6875) (-12.6246, 39.5285) (-12.585, 38.83) knots 0 0 0 0 1 1 1 1
  spline S517 degree 3 poles (-12.585, 38.83) (-12.5453, 38.1315) (-12.6008, 38.33) (-12.585, 38.1156) knots 0 0 0 0 1 1 1 1
  spline S518 degree 3 poles (-12.585, 38.1156) (-12.5691, 37.9013) (-12.5453, 37.7188) (-12.5056, 37.56) knots 0 0 0 0 1 1 1 1
  spline S519 degree 3 poles (-12.5056, 37.56) (-12.4659, 37.4013) (-12.4341, 37.2981) (-12.3468, 37.1631) knots 0 0 0 0 1 1 1 1
  spline S520 degree 3 poles (-12.3468, 37.1631) (-12.2595, 37.0282) (-12.1087, 36.8695) (-11.9896, 36.7663) knots 0 0 0 0 1 1 1 1
  spline S521 degree 3 poles (-11.9896, 36.7663) (-11.8706, 36.6631) (-11.7595, 36.6155) (-11.6325, 36.5678) knots 0 0 0 0 1 1 1 1
  spline S522 degree 3 poles (-11.6325, 36.5678) (-11.5055, 36.5202) (-11.3626, 36.4964) (-11.2356, 36.4885) knots 0 0 0 0 1 1 1 1
  spline S523 degree 3 poles (-11.2356, 36.4885) (-11.1086, 36.4805) (-11.0054, 36.4964) (-10.8784, 36.5281) knots 0 0 0 0 1 1 1 1
  spline S524 degree 3 poles (-10.8784, 36.5281) (-10.7514, 36.5599) (-10.5926, 36.6234) (-10.4815, 36.6869) knots 0 0 0 0 1 1 1 1
  spline S525 degree 3 poles (-10.4815, 36.6869) (-10.3704, 36.7504) (-10.299, 36.806) (-10.2037, 36.925) knots 0 0 0 0 1 1 1 1
  spline S526 degree 3 poles (-10.2037, 36.925) (-10.1085, 37.0441) (-9.9894, 37.2108) (-9.9259, 37.4013) knots 0 0 0 0 1 1 1 1
  spline S527 degree 3 poles (-9.9259, 37.4013) (-9.8624, 37.5918) (-9.8624, 37.4806) (-9.8068, 38.076) knots 0 0 0 0 1 1 1 1
  spline S528 degree 3 poles (-9.8068, 38.076) (-9.7513, 38.6713) (-9.664, 40.2588) (-9.6084, 40.9731) knots 0 0 0 0 1 1 1 1
  spline S529 degree 3 poles (-9.6084, 40.9731) (-9.5528, 41.6875) (-9.4893, 42.0923) (-9.4496, 42.3622) knots 0 0 0 0 1 1 1 1
  spline S530 degree 3 poles (-9.4496, 42.3622) (-9.41, 42.6321) (-9.4258, 42.521) (-9.3703, 42.6003) knots 0 0 0 0 1 1 1 1
  spline S531 degree 3 poles (-9.3703, 42.6003) (-9.3147, 42.6797) (-9.1877, 42.7908) (-9.1321, 42.8385) knots 0 0 0 0 1 1 1 1
  spline S532 degree 3 poles (-9.1321, 42.8385) (-9.0766, 42.8861) (-10.1958, 42.8702) (-9.0131, 42.8781) knots 0 0 0 0 1 1 1 1
  spline S533 degree 3 poles (-9.0131, 42.8781) (-7.8304, 42.8861) (-3.2187, 42.894) (-2.0281, 42.8781) knots 0 0 0 0 1 1 1 1
  spline S534 degree 3 poles (-2.0281, 42.8781) (-0.8375, 42.8623) (-1.9249, 42.8464) (-1.8693, 42.7988) knots 0 0 0 0 1 1 1 1
  spline S535 degree 3 poles (-1.8693, 42.7988) (-1.8138, 42.7511) (-1.7503, 42.6956) (-1.7106, 42.6003) knots 0 0 0 0 1 1 1 1
  spline S536 degree 3 poles (-1.7106, 42.6003) (-1.6709, 42.5051) (-1.6947, 43.0131) (-1.6312, 42.2035) knots 0 0 0 0 1 1 1 1
  spline S537 degree 3 poles (-1.6312, 42.2035) (-1.5677, 41.3938) (-1.409, 38.5522) (-1.3534, 37.7585) knots 0 0 0 0 1 1 1 1
  spline S538 degree 3 poles (-1.3534, 37.7585) (-1.2978, 36.9647) (-1.3216, 37.56) (-1.274, 37.441) knots 0 0 0 0 1 1 1 1
  spline S539 degree 3 poles (-1.274, 37.441) (-1.2264, 37.3219) (-1.155, 37.1552) (-1.0756, 37.0441) knots 0 0 0 0 1 1 1 1
  spline S540 degree 3 poles (-1.0756, 37.0441) (-0.9962, 36.933) (-0.901, 36.8456) (-0.7978, 36.7663) knots 0 0 0 0 1 1 1 1
  spline S541 degree 3 poles (-0.7978, 36.7663) (-0.6946, 36.6869) (-0.5517, 36.6155) (-0.4406, 36.5678) knots 0 0 0 0 1 1 1 1
  spline S542 degree 3 poles (-0.4406, 36.5678) (-0.3295, 36.5202) (-0.2818, 36.4964) (-0.1231, 36.4885) knots 0 0 0 0 1 1 1 1
  spline S543 degree 3 poles (-0.1231, 36.4885) (0.0357, 36.4805) (0.3373, 36.4885) (0.5119, 36.5281) knots 0 0 0 0 1 1 1 1
  spline S544 degree 3 poles (0.5119, 36.5281) (0.6865, 36.5678) (0.8056, 36.6631) (0.9088, 36.7266) knots 0 0 0 0 1 1 1 1
  spline S545 degree 3 poles (0.9088, 36.7266) (1.012, 36.7901) (1.0675, 36.8218) (1.1469, 36.925) knots 0 0 0 0 1 1 1 1
  spline S546 degree 3 poles (1.1469, 36.925) (1.2263, 37.0282) (1.3215, 37.187) (1.385, 37.3616) knots 0 0 0 0 1 1 1 1
  spline S547 degree 3 poles (1.385, 37.3616) (1.4485, 37.5362) (1.4803, 37.7505) (1.5041, 37.9569) knots 0 0 0 0 1 1 1 1
  spline S548 degree 3 poles (1.5041, 37.9569) (1.5279, 38.1633) (1.4724, 38.1395) (1.5041, 38.5919) knots 0 0 0 0 1 1 1 1
  spline S549 degree 3 poles (1.5041, 38.5919) (1.5359, 39.0443) (1.6549, 40.0762) (1.7025, 40.6953) knots 0 0 0 0 1 1 1 1
  spline S550 degree 3 poles (1.7025, 40.6953) (1.7502, 41.3145) (1.7502, 41.9574) (1.7819, 42.2828) knots 0 0 0 0 1 1 1 1
  spline S551 degree 3 poles (1.7819, 42.2828) (1.8137, 42.6083) (1.8454, 42.5368) (1.901, 42.64) knots 0 0 0 0 1 1 1 1
  spline S552 degree 3 poles (1.901, 42.64) (1.9565, 42.7432) (0.9326, 42.8385) (2.1391, 42.8781) knots 0 0 0 0 1 1 1 1
  spline S553 degree 3 poles (2.1391, 42.8781) (3.3456, 42.9178) (7.9255, 42.902) (9.1241, 42.8781) knots 0 0 0 0 1 1 1 1
  spline S554 degree 3 poles (9.1241, 42.8781) (10.3227, 42.8543) (9.259, 42.8226) (9.3225, 42.7591) knots 0 0 0 0 1 1 1 1
  spline S555 degree 3 poles (9.3225, 42.7591) (9.386, 42.6956) (9.4416, 42.6083) (9.4813, 42.4813) knots 0 0 0 0 1 1 1 1
  spline S556 degree 3 poles (9.4813, 42.4813) (9.521, 42.3543) (9.4892, 42.8385) (9.5607, 42.005) knots 0 0 0 0 1 1 1 1
  spline S557 degree 3 poles (9.5607, 42.005) (9.6321, 41.1716) (9.8226, 38.3061) (9.9179, 37.4806) knots 0 0 0 0 1 1 1 1
  spline S558 degree 3 poles (9.9179, 37.4806) (10.0131, 36.6551) (10.0528, 37.1473) (10.1163, 37.0441) knots 0 0 0 0 1 1 1 1
  spline S559 degree 3 poles (10.1163, 37.0441) (10.1798, 36.9409) (10.1798, 36.925) (10.275, 36.8456) knots 0 0 0 0 1 1 1 1
  spline S560 degree 3 poles (10.275, 36.8456) (10.3703, 36.7663) (10.5846, 36.6313) (10.7116, 36.5678) knots 0 0 0 0 1 1 1 1
  spline S561 degree 3 poles (10.7116, 36.5678) (10.8386, 36.5043) (10.8942, 36.4964) (11.0291, 36.4885) knots 0 0 0 0 1 1 1 1
  spline S562 degree 3 poles (11.0291, 36.4885) (11.164, 36.4805) (11.4022, 36.4964) (11.545, 36.5281) knots 0 0 0 0 1 1 1 1
  spline S563 degree 3 poles (11.545, 36.5281) (11.6879, 36.5599) (11.799, 36.6234) (11.9022, 36.6869) knots 0 0 0 0 1 1 1 1
  spline S564 degree 3 poles (11.9022, 36.6869) (12.0054, 36.7504) (12.0848, 36.798) (12.18, 36.925) knots 0 0 0 0 1 1 1 1
  spline S565 degree 3 poles (12.18, 36.925) (12.2753, 37.052) (12.3944, 37.187) (12.4579, 37.441) knots 0 0 0 0 1 1 1 1
  spline S566 degree 3 poles (12.4579, 37.441) (12.5214, 37.695) (12.5293, 37.6632) (12.5769, 38.4331) knots 0 0 0 0 1 1 1 1
  spline S567 degree 3 poles (12.5769, 38.4331) (12.6245, 39.2031) (12.688, 41.3462) (12.7357, 42.0447) knots 0 0 0 0 1 1 1 1
  spline S568 degree 3 poles (12.7357, 42.0447) (12.7833, 42.7432) (12.7992, 42.5051) (12.8547, 42.64) knots 0 0 0 0 1 1 1 1
  spline S569 degree 3 poles (12.8547, 42.64) (12.9103, 42.775) (12.2594, 42.7988) (13.0532, 42.8385) knots 0 0 0 0 1 1 1 1
  spline S570 degree 3 poles (13.0532, 42.8385) (13.8469, 42.8781) (16.7679, 42.902) (17.6172, 42.8781) knots 0 0 0 0 1 1 1 1
  spline S571 degree 3 poles (17.6172, 42.8781) (18.4665, 42.8543) (17.9903, 42.775) (18.1332, 42.6797) knots 0 0 0 0 1 1 1 1
  spline S572 degree 3 poles (18.1332, 42.6797) (18.276, 42.5845) (18.3713, 42.4733) (18.4507, 42.3225) knots 0 0 0 0 1 1 1 1
  spline S573 degree 3 poles (18.4507, 42.3225) (18.53, 42.1717) (18.5935, 43.8862) (18.6094, 41.7669) knots 0 0 0 0 1 1 1 1
  spline S574 degree 3 poles (18.6094, 41.7669) (18.6253, 39.6476) (18.5459, 31.7418) (18.5697, 29.6225) knots 0 0 0 0 1 1 1 1
  spline S575 degree 3 poles (18.5697, 29.6225) (18.5935, 27.5032) (18.7047, 29.1621) (18.7682, 29.0272) knots 0 0 0 0 1 1 1 1
  spline S576 degree 3 poles (18.7682, 29.0272) (18.8317, 28.8923) (18.8317, 28.9002) (18.9269, 28.8288) knots 0 0 0 0 1 1 1 1
  spline S577 degree 3 poles (18.9269, 28.8288) (19.0222, 28.7573) (18.919, 28.7415) (19.3238, 28.5906) knots 0 0 0 0 1 1 1 1
  spline S578 degree 3 poles (19.3238, 28.5906) (19.7286, 28.4398) (20.689, 28.17) (21.3479, 27.916) knots 0 0 0 0 1 1 1 1
  spline S579 degree 3 poles (21.3479, 27.916) (22.0067, 27.662) (22.6734, 27.3921) (23.2925, 27.0825) knots 0 0 0 0 1 1 1 1
  spline S580 degree 3 poles (23.2925, 27.0825) (23.9117, 26.773) (24.5467, 26.3999) (25.0785, 26.0506) knots 0 0 0 0 1 1 1 1
  spline S581 degree 3 poles (25.0785, 26.0506) (25.6103, 25.7014) (25.904, 25.5109) (26.5072, 24.9791) knots 0 0 0 0 1 1 1 1
  spline S582 degree 3 poles (26.5072, 24.9791) (27.1105, 24.4473) (28.1106, 23.4789) (28.69, 22.8756) knots 0 0 0 0 1 1 1 1
  spline S583 degree 3 poles (28.69, 22.8756) (29.2695, 22.2724) (29.5473, 21.9311) (29.9997, 21.3675) knots 0 0 0 0 1 1 1 1
  spline S584 degree 3 poles (29.9997, 21.3675) (30.4522, 20.804) (30.9046, 20.2166) (31.3888, 19.5022) knots 0 0 0 0 1 1 1 1
  spline S585 degree 3 poles (31.3888, 19.5022) (31.873, 18.7878) (32.4524, 17.8671) (32.8969, 17.0813) knots 0 0 0 0 1 1 1 1
  spline S586 degree 3 poles (32.8969, 17.0813) (33.3414, 16.2955) (33.6827, 15.6208) (34.0479, 14.7794) knots 0 0 0 0 1 1 1 1
  spline S587 degree 3 poles (34.0479, 14.7794) (34.413, 13.938) (34.8257, 12.795) (35.0797, 12.041) knots 0 0 0 0 1 1 1 1
  spline S588 degree 3 poles (35.0797, 12.041) (35.3337, 11.2869) (35.4369, 10.7471) (35.556, 10.255) knots 0 0 0 0 1 1 1 1
  spline S589 degree 3 poles (35.556, 10.255) (35.675, 9.7629) (35.6909, 9.7232) (35.7941, 9.1041) knots 0 0 0 0 1 1 1 1
  spline S590 degree 3 poles (35.7941, 9.1041) (35.8973, 8.485) (36.0799, 7.1753) (36.1513, 6.5641) knots 0 0 0 0 1 1 1 1
  spline S591 degree 3 poles (36.1513, 6.5641) (36.2227, 5.9529) (36.2148, 6.1275) (36.2307, 5.4528) knots 0 0 0 0 1 1 1 1
  spline S592 degree 3 poles (36.2307, 5.4528) (36.2465, 4.7781) (36.2545, 3.3573) (36.2307, 2.516) knots 0 0 0 0 1 1 1 1
  spline S593 degree 3 poles (36.2307, 2.516) (36.2069, 1.6746) (36.1354, 1.0634) (36.0719, 0.4125) knots 0 0 0 0 1 1 1 1
  spline S594 degree 3 poles (36.0719, 0.4125) (36.0084, -0.2384) (35.929, -0.794) (35.8338, -1.3734) knots 0 0 0 0 1 1 1 1
  spline S595 degree 3 poles (35.8338, -1.3734) (35.7385, -1.9529) (35.6909, -2.31) (35.5163, -3.08) knots 0 0 0 0 1 1 1 1
  spline S596 degree 3 poles (35.5163, -3.08) (35.3417, -3.8499) (35.0004, -5.1993) (34.7622, -6.0169) knots 0 0 0 0 1 1 1 1
  spline S597 degree 3 poles (34.7622, -6.0169) (34.5241, -6.8344) (34.3019, -7.4218) (34.0875, -8.0012) knots 0 0 0 0 1 1 1 1
  spline S598 degree 3 poles (34.0875, -8.0012) (33.8732, -8.5807) (33.7621, -8.8744) (33.4922, -9.4697) knots 0 0 0 0 1 1 1 1
  spline S599 degree 3 poles (33.4922, -9.4697) (33.2224, -10.065) (32.8493, -10.8508) (32.4604, -11.5731) knots 0 0 0 0 1 1 1 1
  spline S600 degree 3 poles (32.4604, -11.5731) (32.0714, -12.2954) (31.5952, -13.105) (31.1507, -13.7956) knots 0 0 0 0 1 1 1 1
  spline S601 degree 3 poles (31.1507, -13.7956) (30.7062, -14.4862) (30.1505, -15.2561) (29.8013, -15.7403) knots 0 0 0 0 1 1 1 1
  spline S602 degree 3 poles (29.8013, -15.7403) (29.452, -16.2245) (29.4441, -16.2245) (29.0472, -16.6928) knots 0 0 0 0 1 1 1 1
  spline S603 degree 3 poles (29.0472, -16.6928) (28.6504, -17.1611) (27.9042, -18.0342) (27.42, -18.5581) knots 0 0 0 0 1 1 1 1
  spline S604 degree 3 poles (27.42, -18.5581) (26.9359, -19.082) (26.6263, -19.3757) (26.15, -19.8281) knots 0 0 0 0 1 1 1 1
  spline S605 degree 3 poles (26.15, -19.8281) (25.6738, -20.2805) (25.3007, -20.6615) (24.5625, -21.2569) knots 0 0 0 0 1 1 1 1
  spline S606 degree 3 poles (24.5625, -21.2569) (23.8244, -21.8522) (22.5861, -22.7967) (21.705, -23.4) knots 0 0 0 0 1 1 1 1
  spline S607 degree 3 poles (21.705, -23.4) (20.824, -24.0032) (19.9112, -24.5033) (19.2841, -24.8684) knots 0 0 0 0 1 1 1 1
  spline S608 degree 3 poles (-29.1346, -45.9028) (-28.9838, -45.8949) (-28.9045, -45.8552) (-28.8171, -45.8234) knots 0 0 0 0 1 1 1 1
  spline S609 degree 3 poles (-28.8171, -45.8234) (-28.7298, -45.7917) (-28.7457, -45.8155) (-28.6187, -45.7044) knots 0 0 0 0 1 1 1 1
  spline S610 degree 3 poles (-28.6187, -45.7044) (-28.4917, -45.5932) (-28.7378, -46.0377) (-28.0631, -45.1487) knots 0 0 0 0 1 1 1 1
  spline S611 degree 3 poles (-28.0631, -45.1487) (-27.3884, -44.2597) (-25.6977, -41.8944) (-24.5706, -40.3862) knots 0 0 0 0 1 1 1 1
  spline S612 degree 3 poles (-24.5706, -40.3862) (-23.4435, -38.8781) (-22.1893, -37.3144) (-21.2765, -36.1) knots 0 0 0 0 1 1 1 1
  spline S613 degree 3 poles (-21.2765, -36.1) (-20.3637, -34.8855) (-19.5541, -33.7267) (-19.0937, -33.1234) knots 0 0 0 0 1 1 1 1
  spline S614 degree 3 poles (-19.0937, -33.1234) (-18.6333, -32.5202) (-18.6968, -32.7107) (-18.5381, -32.4884) knots 0 0 0 0 1 1 1 1
  spline S615 degree 3 poles (-18.5381, -32.4884) (-18.3793, -32.2662) (-18.2206, -31.9804) (-18.1412, -31.8137) knots 0 0 0 0 1 1 1 1
  spline S616 degree 3 poles (-18.1412, -31.8137) (-18.0618, -31.647) (-18.0777, -31.6074) (-18.0618, -31.4962) knots 0 0 0 0 1 1 1 1
  spline S617 degree 3 poles (-18.0618, -31.4962) (-18.046, -31.3851) (-18.0301, -31.2819) (-18.0618, -31.139) knots 0 0 0 0 1 1 1 1
  spline S618 degree 3 poles (-18.0618, -31.139) (-18.0936, -30.9962) (-18.1571, -30.7819) (-18.2603, -30.6231) knots 0 0 0 0 1 1 1 1
  spline S619 degree 3 poles (-18.2603, -30.6231) (-18.3635, -30.4644) (-18.046, -30.7184) (-18.6571, -30.1865) knots 0 0 0 0 1 1 1 1
  spline S620 degree 3 poles (-18.6571, -30.1865) (-19.2683, -29.6547) (-21.221, -28.0434) (-21.9115, -27.4481) knots 0 0 0 0 1 1 1 1
  spline S621 degree 3 poles (-21.9115, -27.4481) (-22.6021, -26.8528) (-22.5703, -26.8052) (-22.7846, -26.6147) knots 0 0 0 0 1 1 1 1
  spline S622 degree 3 poles (-22.7846, -26.6147) (-22.999, -26.4242) (-22.364, -27.0909) (-23.2212, -26.2972) knots 0 0 0 0 1 1 1 1
  spline S623 degree 3 poles (-23.2212, -26.2972) (-24.0785, -25.5034) (-26.5391, -23.2015) (-27.944, -21.8522) knots 0 0 0 0 1 1 1 1
  spline S624 degree 3 poles (-27.944, -21.8522) (-29.349, -20.5028) (-30.9206, -18.8994) (-31.635, -18.2009) knots 0 0 0 0 1 1 1 1
  spline S625 degree 3 poles (-31.635, -18.2009) (-32.3493, -17.5024) (-32.0795, -17.7961) (-32.2303, -17.685) knots 0 0 0 0 1 1 1 1
  spline S626 degree 3 poles (-32.2303, -17.685) (-32.3811, -17.5739) (-32.4446, -17.5659) (-32.5478, -17.5262) knots 0 0 0 0 1 1 1 1
  spline S627 degree 3 poles (-32.5478, -17.5262) (-32.651, -17.4865) (-32.7541, -17.4627) (-32.8653, -17.4469) knots 0 0 0 0 1 1 1 1
  spline S628 degree 3 poles (-32.8653, -17.4469) (-32.9764, -17.431) (-33.1113, -17.431) (-33.2225, -17.4469) knots 0 0 0 0 1 1 1 1
  spline S629 degree 3 poles (-33.2225, -17.4469) (-33.3336, -17.4627) (-33.405, -17.4707) (-33.54, -17.5262) knots 0 0 0 0 1 1 1 1
  spline S630 degree 3 poles (-33.54, -17.5262) (-33.6749, -17.5818) (-32.3573, -16.4388) (-34.0162, -17.804) knots 0 0 0 0 1 1 1 1
  spline S631 degree 3 poles (-34.0162, -17.804) (-35.6751, -19.1693) (-41.8585, -24.3525) (-43.5015, -25.7415) knots 0 0 0 0 1 1 1 1
  spline S632 degree 3 poles (-43.5015, -25.7415) (-45.1446, -27.1306) (-43.7317, -25.9955) (-43.8984, -26.1384) knots 0 0 0 0 1 1 1 1
  spline S633 degree 3 poles (-43.8984, -26.1384) (-44.0651, -26.2813) (-44.3191, -26.4321) (-44.4937, -26.575) knots 0 0 0 0 1 1 1 1
  spline S634 degree 3 poles (-44.4937, -26.575) (-44.6683, -26.7179) (-44.835, -26.9084) (-44.9303, -27.0115) knots 0 0 0 0 1 1 1 1
  spline S635 degree 3 poles (-44.9303, -27.0115) (-45.0255, -27.1147) (-45.0176, -27.1306) (-45.0493, -27.21) knots 0 0 0 0 1 1 1 1
  spline S636 degree 3 poles (-45.0493, -27.21) (-45.0811, -27.2894) (-45.1128, -27.3529) (-45.1287, -27.4878) knots 0 0 0 0 1 1 1 1
  spline S637 degree 3 poles (-45.1287, -27.4878) (-45.1446, -27.6227) (-45.1605, -27.8291) (-45.1287, -28.0037) knots 0 0 0 0 1 1 1 1
  spline S638 degree 3 poles (-45.1287, -28.0037) (-45.097, -28.1784) (-45.0096, -28.3847) (-44.9303, -28.5197) knots 0 0 0 0 1 1 1 1
  spline S639 degree 3 poles (-44.9303, -28.5197) (-44.8509, -28.6546) (-44.7953, -28.7181) (-44.6525, -28.7975) knots 0 0 0 0 1 1 1 1
  spline S640 degree 3 poles (-44.6525, -28.7975) (-44.5096, -28.8769) (-44.3191, -28.9483) (-44.0571, -28.9959) knots 0 0 0 0 1 1 1 1
  spline S641 degree 3 poles (-44.0571, -28.9959) (-43.7952, -29.0435) (-43.4698, -29.0594) (-43.1046, -29.0753) knots 0 0 0 0 1 1 1 1
  spline S642 degree 3 poles (-43.1046, -29.0753) (-42.7395, -29.0912) (-42.2395, -29.0594) (-41.8743, -29.0753) knots 0 0 0 0 1 1 1 1
  spline S643 degree 3 poles (-41.8743, -29.0753) (-41.5092, -29.0912) (-41.7314, -29.1229) (-40.9218, -29.1547) knots 0 0 0 0 1 1 1 1
  spline S644 degree 3 poles (-40.9218, -29.1547) (-40.1122, -29.1864) (-37.6595, -29.242) (-36.9928, -29.2737) knots 0 0 0 0 1 1 1 1
  spline S645 degree 3 poles (-36.9928, -29.2737) (-36.326, -29.3055) (-36.9213, -29.2975) (-36.9134, -29.3531) knots 0 0 0 0 1 1 1 1
  spline S646 degree 3 poles (-36.9134, -29.3531) (-36.9055, -29.4087) (-36.8737, -29.4087) (-36.9531, -29.5912) knots 0 0 0 0 1 1 1 1
  spline S647 degree 3 poles (-36.9531, -29.5912) (-37.0325, -29.7738) (-37.1912, -30.0119) (-37.3896, -30.4644) knots 0 0 0 0 1 1 1 1
  spline S648 degree 3 poles (-37.3896, -30.4644) (-37.5881, -30.9168) (-37.9532, -31.8614) (-38.1437, -32.29) knots 0 0 0 0 1 1 1 1
  spline S649 degree 3 poles (-38.1437, -32.29) (-38.3342, -32.7186) (-38.4374, -32.8059) (-38.5406, -33.044) knots 0 0 0 0 1 1 1 1
  spline S650 degree 3 poles (-38.5406, -33.044) (-38.6438, -33.2822) (-38.6835, -33.5044) (-38.7787, -33.7187) knots 0 0 0 0 1 1 1 1
  spline S651 degree 3 poles (-38.7787, -33.7187) (-38.8739, -33.933) (-38.993, -34.0759) (-39.0962, -34.314) knots 0 0 0 0 1 1 1 1
  spline S652 degree 3 poles (-39.0962, -34.314) (-39.1994, -34.5522) (-39.3185, -34.9252) (-39.4137, -35.1475) knots 0 0 0 0 1 1 1 1
  spline S653 degree 3 poles (-39.4137, -35.1475) (-39.5089, -35.3697) (-39.5963, -35.4491) (-39.6915, -35.6634) knots 0 0 0 0 1 1 1 1